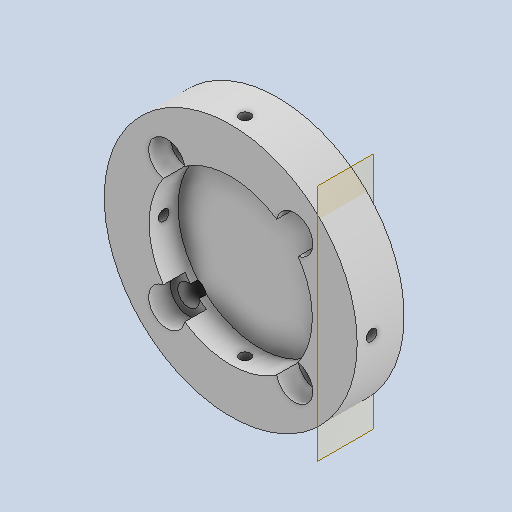
# Autodesk Inventor part: 零件2
Saved by Autodesk Inventor 2025 (Build 290162000, 162)
## iProperties
Created: 2026-11-03
Part Number: 零件2
Material: 常规
Document SubType Name: Modeling
Designer: test
Density: 1 g/cm^3
Appearance: 默认
Author: test
Autodesk Inventor part; units mm, degrees
ref_plane "XZ Plane" through (0, 0, 0) normal (0, 1, 0) x (-1, 0, 0)
ref_plane "XY Plane" through (0, 0, 0) normal (0, 0, 1) x (1, 0, 0)
sketch "草图1" plane through (0, 0, 0) normal (0, 0, 1) x (1, 0, 0)
  circle A0 centre (0, 0) radius 35
  dimension "d0" = 70
  constraints: 1 centre point, 1 coincident
  measures "d0" diameter of A0
extrude "拉伸1" add sketch "草图1" along normal blind 14
sketch "草图2" plane through (0, 0, 14) normal (0, 0, 1) x (1, 0, 0)
  circle A0 centre (0, 0) radius 25
  line L0 (-17.6777, -17.6777) -> (17.6777, -17.6777)
  line L1 (17.6777, -17.6777) -> (17.6777, 17.6777)
  line L2 (17.6777, 17.6777) -> (-17.6777, 17.6777)
  line L3 (-17.6777, 17.6777) -> (-17.6777, -17.6777)
  line L4 (-17.6777, -17.6777) -> (17.6777, 17.6777) construction
  line L5 (17.6777, -17.6777) -> (-17.6777, 17.6777) construction
  circle A1 centre (-17.6777, 17.6777) radius 3
  circle A2 centre (-17.6777, -17.6777) radius 3
  circle A3 centre (17.6777, -17.6777) radius 3
  circle A4 centre (17.6777, 17.6777) radius 3
  dimension "d3" = 50
  dimension "d4" = 6
  dimension "d5" = 6
  dimension "d6" = 6
  dimension "d7" = 6
  constraints: 12 end point, 5 coincident, 4 centre point, 2 midpoint, 2 parallel, 2 perpendicular, 1 horizontal, 3 other
  measures "d4" diameter of A1
  measures "d5" diameter of A2
  measures "d6" diameter of A3
  measures "d7" diameter of A4
extrude "拉伸2" cut sketch "草图2" against normal through all contours A4 L1 A0 | A0 A4 | A3 A0 | A0 L1 A3 | L2 A4 A0 | L1 A4 L2 | A0 A3 L0 | L0 A3 L1 | A1 L2 A0 | A0 A1 | A1 L3 L2 | A2 A0 | A0 L0 A2 | L0 L3 A2 | L3 A1 A0 | A0 A2 L3
sketch "草图3" plane through (0, 0, 14) normal (0, 0, 1) x (1, 0, 0)
  circle A0 centre (0, 0) radius 22.575
  dimension "d10" = 45.15
  constraints: 1 centre point, 1 coincident
  measures "d10" diameter of A0
extrude "拉伸3" cut sketch "草图3" against normal blind 8
ref_plane "工作平面1" through (24.75, 0, 0) normal (1, 0, 0) x (0, 1, 0)
sketch "草图5" plane through (24.75, 0, 0) normal (1, 0, 0) x (0, 1, 0)
  circle A0 centre (0, 10) radius 1.5
  line L0 (35, 14) -> (-35, 14) projected
  point P0 (0, 0)
  dimension "d14" = 3
  dimension "d15" = 4
  constraints: 1 centre point
  measures "d14" diameter of A0
  measures "d15" distance from line of L0 A0.centre
extrude "拉伸4" cut sketch "草图5" along normal blind 17 and the other way blind 68.5
thread "螺纹1" size "M3x0.5" designation "M3" class "6H" standard "GB Metric profile" length 15.103
sketch "草图6" plane through (0, 0, 0) normal (0, 1, 0) x (-1, 0, 0)
  circle A0 centre (0, 10) radius 1.5
  line L0 (35, 14) -> (-35, 14) projected
  point P0 (0, 0)
  dimension "d22" = 3
  dimension "d23" = 4
  constraints: 1 centre point
  measures "d22" diameter of A0
  measures "d23" distance from line of L0 A0.centre
extrude "拉伸5" cut sketch "草图6" along normal blind 39.5 and the other way blind 36.75
thread "螺纹2" size "M3x0.5" designation "M3" class "6H" standard "GB Metric profile" length 15.103
thread "螺纹3" size "M3x0.5" designation "M3" class "6H" standard "GB Metric profile" length 15.103
thread "螺纹4" size "M3x0.5" designation "M3" class "6H" standard "GB Metric profile" length 15.103
sketch "草图7" plane through (0, 0, 14) normal (0, 0, 1) x (1, 0, 0)
  arc A0 (17.1048, -14.7329) -> (17.1048, 14.7329) centre (0, 0) ccw projected
  arc A1 (14.7329, -17.1048) -> (17.1048, -14.7329) centre (17.6777, -17.6777) ccw projected
  arc A2 (-14.7329, -17.1048) -> (14.7329, -17.1048) centre (0, 0) ccw projected
  arc A3 (-17.1048, -14.7329) -> (-14.7329, -17.1048) centre (-17.6777, -17.6777) ccw projected
  arc A4 (-17.1048, 14.7329) -> (-17.1048, -14.7329) centre (0, 0) ccw projected
  arc A5 (-14.7329, 17.1048) -> (-17.1048, 14.7329) centre (-17.6777, 17.6777) ccw projected
  arc A6 (14.7329, 17.1048) -> (-14.7329, 17.1048) centre (0, 0) ccw projected
  arc A7 (17.1048, 14.7329) -> (14.7329, 17.1048) centre (17.6777, 17.6777) ccw projected
  circle A8 centre (0, 0) radius 35 projected
  circle A9 centre (-17.6777, 17.6777) radius 5.05
  circle A10 centre (17.6777, 17.6777) radius 5.05
  circle A11 centre (-17.6777, -17.6777) radius 5.05
  circle A12 centre (17.6777, -17.6777) radius 5.05
  point P0 (-18.6489, -12.722)
  point P1 (-12.722, -18.6489)
  point P2 (12.722, -18.6489)
  point P3 (18.6489, -12.722)
  point P4 (18.6489, 12.722)
  point P5 (12.722, 18.6489)
  point P6 (-12.722, 18.6489)
  point P7 (-18.6489, 12.722)
  dimension "d34" = 10.1
  dimension "d35" = 10.1
  dimension "d36" = 10.1
  dimension "d37" = 10.1
  constraints: 4 centre point, 4 coincident
  measures "d34" diameter of A9
  measures "d35" diameter of A10
  measures "d36" diameter of A11
  measures "d37" diameter of A12
extrude "拉伸6" cut sketch "草图7" against normal blind 6 contours A0 A12 A2 A1 | A0 A7 A6 A10 | A11 A4 A3 A2 | A6 A5 A4 A9 picked at (21.9779, -18.2648) picked at (21.9779, 18.2648) picked at (-13.9754, -19.9467) picked at (-19.9467, 13.9754)
sketch "草图8" plane through (0, 0, 0) normal (0, 0, -1) x (-1, 0, 0)
  circle A0 centre (-17.6777, -17.6777) radius 3 projected
  circle A1 centre (17.6777, -17.6777) radius 3 projected
  circle A2 centre (-17.6777, 17.6777) radius 3 projected
  circle A3 centre (17.6777, 17.6777) radius 3 projected
  circle A4 centre (0, 0) radius 35 projected
extrude "拉伸7" cut sketch "草图8" against normal blind 1
equation "\"d8\" = d5"
